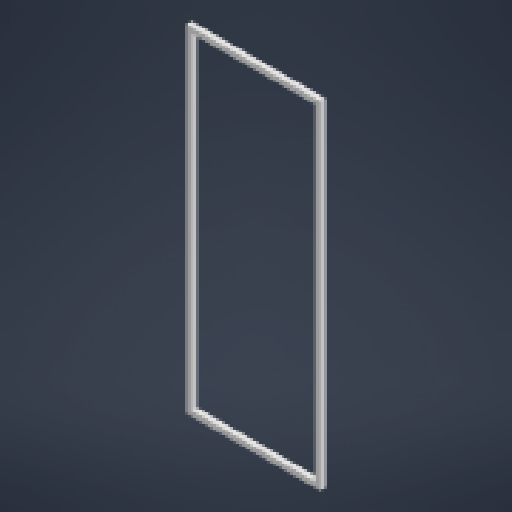
# Autodesk Inventor part: joint
Saved by Autodesk Inventor 2026.1 (Build 301233020, 233B)
## iProperties
Created: 2026-06-05
Part Number: joint
Material: Générique
Document SubType Name: Modeling
Designer: matpo
Density: 1 g/cm^3
Appearance: Par défaut
Author: matpo
Autodesk Inventor part; units mm, degrees
ref_plane "YZ Plane" through (0, 0, 0) normal (1, 0, 0) x (0, 1, 0)
ref_plane "XZ Plane" through (0, 0, 0) normal (0, 1, 0) x (-1, 0, 0)
ref_plane "XY Plane" through (0, 0, 0) normal (0, 0, 1) x (1, 0, 0)
sketch "Esquisse1" plane through (0, 0, 0) normal (0, 0, 1) x (1, 0, 0)
  line L0 (-23.1, -17.5) -> (-43.1, -17.5) projected
  line L1 (-23.1, 32.5) -> (-23.1, -17.5) projected
  line L2 (-43.1, 32.5) -> (-23.1, 32.5) projected
  line L3 (-43.1, -17.5) -> (-43.1, 32.5) projected
  line L4 (-42.1, -16.5) -> (-24.1, -16.5) projected
  line L5 (-42.1, 31.5) -> (-42.1, -16.5) projected
  line L6 (-24.1, 31.5) -> (-42.1, 31.5) projected
  line L7 (-24.1, -16.5) -> (-24.1, 31.5) projected
  line L8 (-23.2, -17.4) -> (-43, -17.4)
  line L9 (-43, -17.4) -> (-43, 32.4)
  line L10 (-43, 32.4) -> (-23.2, 32.4)
  line L11 (-23.2, 32.4) -> (-23.2, -17.4)
  line L12 (-24, 31.6) -> (-42.2, 31.6)
  line L13 (-42.2, 31.6) -> (-42.2, -16.6)
  line L14 (-42.2, -16.6) -> (-24, -16.6)
  line L15 (-24, -16.6) -> (-24, 31.6)
  point P0 (0, 0)
  dimension "d0" = 0.1
  dimension "d1" = 0.1
  constraints: 16 end point, 6 other
  measures "d0" distance between parallel lines of L1 L11
  measures "d1" distance between parallel lines of L7 L15
extrude "Extrusion1" add sketch "Esquisse1" along normal mid plane 0.8 contours L8 L9 L10 L11
